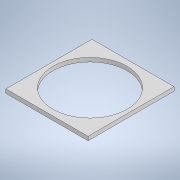
# Autodesk Inventor part: Suport_felinar_general
Saved by Autodesk Inventor 2022.6 (Build 266554000, 554)
## iProperties
Created: 2025-06-12
Part Number: Suport_felinar_general
Material: Generic
Document SubType Name: Modeling
Designer: Dragos Macovei
Density: 1 g/cm^3
Appearance: Default
Author: Dragos Macovei
Autodesk Inventor part; units mm, degrees
ref_plane "YZ Plane" through (0, 0, 0) normal (1, 0, 0) x (0, 1, 0)
ref_plane "XZ Plane" through (0, 0, 0) normal (0, 1, 0) x (-1, 0, 0)
ref_plane "XY Plane" through (0, 0, 0) normal (0, 0, 1) x (1, 0, 0)
sketch "Sketch1" plane through (0, 0, 0) normal (0, 1, 0) x (-1, 0, 0)
  circle A0 centre (0, 0) radius 95
  circle A1 centre (0, 0) radius 105
  line L0 (105, 110) -> (-105, 110)
  line L1 (-105, 110) -> (-105, -110)
  line L2 (-105, -110) -> (105, -110)
  line L3 (105, -110) -> (105, 110)
  dimension "d0" = 190
  dimension "d1" = 210
  dimension "d2" = 210
  dimension "d3" = 220
  dimension "d4" = 110
  constraints: 8 end point, 2 centre point, 2 coincident, 2 parallel, 1 horizontal, 1 perpendicular, 1 tangent
  measures "d0" diameter of A0
  measures "d1" diameter of A1
  measures "d2" distance of L2.end L1.end
  measures "d3" distance of L1.end L0.end
  measures "d4" distance from line of point (0, 0) L0
extrude "Extrusion1" add sketch "Sketch1" along normal blind 10
body "Solid1"
